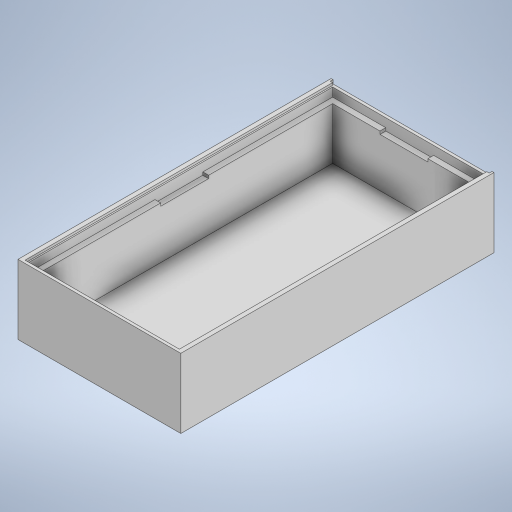
# Autodesk Inventor part: Clockbox01
Saved by Autodesk Inventor 2024 (Build 280153000, 153)
## iProperties
Created: 2026-09-17
Part Number: Clockbox01
Material: Generic
Document SubType Name: Modeling
Designer: Ross
Density: 1 g/cm^3
Appearance: Default
Author: Ross
Autodesk Inventor part; units mm, degrees
ref_plane "YZ Plane" through (0, 0, 0) normal (1, 0, 0) x (0, 1, 0)
ref_plane "XZ Plane" through (0, 0, 0) normal (0, 1, 0) x (-1, 0, 0)
ref_plane "XY Plane" through (0, 0, 0) normal (0, 0, 1) x (1, 0, 0)
sketch "Sketch1" plane through (0, 0, 0) normal (0, 1, 0) x (-1, 0, 0)
  line L0 (170, 327) -> (-170, 327)
  line L1 (-170, 327) -> (-170, -327)
  line L2 (-170, -327) -> (170, -327)
  line L3 (170, -327) -> (170, 327)
  point P0 (0, 0)
  dimension "d0" = 340
  dimension "d1" = 654
  dimension "d2" = 327
  dimension "d3" = 170
  constraints: 8 end point, 2 parallel, 1 horizontal, 1 perpendicular
  measures "d0" distance of L2.end L1.end
  measures "d1" distance of L1.end L0.end
  measures "d2" distance from line of point (0, 0) L0
  measures "d3" distance from line of point (0, 0) L3
extrude "Extrusion1" add sketch "Sketch1" along normal blind 145
sketch "Sketch2" plane through (0, 145, 0) normal (0, 1, 0) x (1, 0, 0)
  line L0 (-161, -321) -> (161, -321)
  line L1 (161, -321) -> (161, 321)
  line L2 (161, 321) -> (-161, 321)
  line L3 (-161, 321) -> (-161, -321)
  point P0 (0, 0)
  dimension "d6" = 322
  dimension "d7" = 642
  dimension "d8" = 161
  dimension "d9" = 321
  constraints: 8 end point, 2 parallel, 1 horizontal, 1 perpendicular
  measures "d6" distance of L2.end L1.end
  measures "d7" distance of L1.end L0.end
  measures "d8" distance from line of point (0, 0) L3
  measures "d9" distance from line of point (0, 0) L0
extrude "Extrusion2" cut sketch "Sketch2" against normal blind 26
sketch "Sketch3" plane through (0, 119, 0) normal (0, 1, 0) x (1, 0, 0)
  line L0 (-149, -309) -> (149, -309)
  line L1 (149, -309) -> (149, 309)
  line L2 (149, 309) -> (-149, 309)
  line L3 (-149, 309) -> (-149, -309)
  line L4 (161, -321) -> (-161, -321) projected
  line L5 (-161, -321) -> (-161, 321) projected
  line L6 (-161, 321) -> (161, 321) projected
  line L7 (161, 321) -> (161, -321) projected
  point P0 (0, 0)
  dimension "d12" = 12
  dimension "d13" = 12
  dimension "d14" = 12
  dimension "d15" = 12
  constraints: 8 end point, 2 parallel, 1 horizontal, 1 perpendicular
  measures "d12" distance between parallel lines of L0 L4
  measures "d13" distance between parallel lines of L3 L5
  measures "d14" distance between parallel lines of L6 L2
  measures "d15" distance between parallel lines of L7 L1
extrude "Extrusion3" cut sketch "Sketch3" against normal blind 108 contours L3 L2 L1 L0
sketch "Sketch4" plane through (170, 0, -327) normal (0, 0, -1) x (-1, 0, 0)
  line L0 (336, 140) -> (4, 140)
  line L1 (4, 140) -> (4, 137)
  line L2 (4, 137) -> (336, 137)
  line L3 (336, 137) -> (336, 140)
  line L4 (340, 0) -> (340, 145) projected
  line L5 (0, 145) -> (340, 145) projected
  point P0 (170, 0)
  point P1 (336, 138.5)
  dimension "d18" = 332
  dimension "d19" = 3
  dimension "d20" = 4
  dimension "d21" = 5
  constraints: 8 end point, 2 parallel, 1 horizontal, 1 midpoint, 1 perpendicular
  measures "d18" distance of L2.end L1.end
  measures "d19" distance of L1.end L0.end
  measures "d20" distance from line of point (336, 138.5) L4
  measures "d21" distance between parallel lines of L0 L5
extrude "Extrusion4" cut sketch "Sketch4" against normal blind 652
sketch "Sketch5" plane through (170, 0, -327) normal (0, 0, -1) x (-1, 0, 0)
  line L0 (4, 147.5768) -> (336, 147.5768)
  line L1 (336, 147.5768) -> (336, 138.29)
  line L2 (336, 138.29) -> (4, 138.29)
  line L3 (4, 138.29) -> (4, 147.5768)
  line L4 (0, 0) -> (0, 145) projected
  line L5 (340, 0) -> (340, 145) projected
  point P0 (170, 0)
  point P1 (336, 142.9334)
  dimension "d26" = 4
  dimension "d27" = 4
  constraints: 8 end point, 2 parallel, 1 horizontal, 1 midpoint, 1 perpendicular
  measures "d26" distance between parallel lines of L4 L3
  measures "d27" distance from line of point (336, 142.933) L5
extrude "Extrusion5" cut sketch "Sketch5" against normal blind 6
sketch "Sketch6" plane through (161, 119, 321) normal (0, 0, -1) x (-1, 0, 0)
  point P0 (161, -119)
sketch "Sketch7" plane through (0, 119, 0) normal (0, 1, 0) x (1, 0, 0)
  line L0 (-50, -321) -> (50, -321)
  line L1 (50, -321) -> (50, -301)
  line L2 (50, -301) -> (-50, -301)
  line L3 (-50, -301) -> (-50, -321)
  line L4 (149, -309) -> (-149, -309) projected
  line L5 (149, 309) -> (149, -309) projected
  line L6 (160.9974, -50) -> (140.9974, -50)
  line L7 (140.9974, -50) -> (140.9974, 50)
  line L8 (140.9974, 50) -> (160.9974, 50)
  line L9 (160.9974, 50) -> (160.9974, -50)
  line L10 (-161, 321) -> (161, 321) projected
  line L11 (-50, 321) -> (50, 321)
  line L12 (50, 321) -> (50, 303.3178)
  line L13 (50, 303.3178) -> (-50, 303.3178)
  line L14 (-50, 303.3178) -> (-50, 321)
  line L15 (-161, -50) -> (-141, -50)
  line L16 (-141, -50) -> (-141, 50)
  line L17 (-141, 50) -> (-161, 50)
  line L18 (-161, 50) -> (-161, -50)
  point P0 (0, 0)
  dimension "d28" = 100
  dimension "d29" = 20
  dimension "d30" = 50
  dimension "d31" = 8
  dimension "d32" = 20
  dimension "d33" = 100
  dimension "d34" = 50
  dimension "d35" = 100
  dimension "d36" = 50
  dimension "d37" = 20
  dimension "d38" = 100
  dimension "d39" = 50
  constraints: 32 end point, 8 parallel, 4 horizontal, 4 perpendicular, 1 point on line
  measures "d28" distance of L2.end L1.end
  measures "d29" distance of L1.end L0.end
  measures "d30" distance from line of point (0, 0) L3
  measures "d31" distance between parallel lines of L2 L4
  measures "d32" distance of L7.end L8.end
  measures "d33" distance of L6.end L7.end
  measures "d34" distance from line of L6 point (0, 0)
  measures "d35" distance of L12.end L13.end
  measures "d36" distance from line of point (0, 0) L14
  measures "d37" distance of L17.end L16.end
  measures "d38" distance of L16.end L15.end
  measures "d39" distance from line of point (0, 0) L15
extrude "Extrusion6" cut sketch "Sketch7" against normal blind 6
body "Solid1"
